Autodesk Fusion 360 part; units mm, degrees
(part 2 of 2)
equation "outer_t = skin_t + bond_t + frame_t" comment "DECIDED: PM ruling 2026-10-31: ACP 3 + bond line 3 + frame 40, walls and ceiling (was 43)"
equation "cav_gap = 4 mm" comment "DECIDED: D-16, D-42: the gap between the outer panel and the lining cassette in the wall and ceiling stack"
equation "cass_t = 34 mm" comment "SOURCE: layout study B1 final list L-CASS 34 (tray + 25 gap + felt 9)"
equation "stack_t = outer_t + cav_gap + cass_t" comment "CALCULATION: D-16, D-42 stack, walls and ceiling: outer panel + cavity gap + cassette (PM ruling 2026-10-31 on outer_t)"
equation "wall_depth = 1495 mm" comment "DECIDED: PM ruling pass C: side walls start at the decor back plate (Y -645), as v1 (1496)"
equation "lin_gap = 4 mm" comment "ASSUMPTION: PM ruling pass C: gap above the upper side linings so they stay floating (= the 4 mm stack gap)"
equation "seam_gap = 2.26 mm" comment "DECIDED: PM ruling 2026-10-31 (Mechanical Checker F-001, F-005): the Joints Engineer's 2.26 mm at all nine site seam types, set by a metal stop (1.5 stop washer + 0.76 rivnut head; joints register section 2.8)"
equation "floor_t = 0 mm" comment "DECIDED: D-132 (PM ruling 2026-11-01): no floor; people stand on the room floor (was 9)"
equation "thresh_h = 0 mm" comment "DECIDED: D-132 (PM ruling 2026-11-01): no threshold, no step at the door; the door's drop seal closes on the room floor (was 13)"
equation "thresh_d = 60 mm" comment "SOURCE: layout study B1 list B-THRESH 1176 x 60 x 20"
equation "decor_d = 205 mm" comment "SOURCE: v1 geometry per the PM ruling on D-39 (as v1; the drawings win): v1 decor-frame drawing frames 191 (left) and 197 (right) deep plus ACP and back plate = the v1 STEP shell, Y -850 to -645 = 205. D-39 and the B1 list say 230-235 (v1 BOM); see BUILD-RECORD-P02"
equation "dl_w = 278 mm" comment "SOURCE: B1 list F-DL 278 (v1 BOM DL)"
equation "dr_w = 1016 mm" comment "SOURCE: B1 list F-DR 1016 (v1 STEP solid 78)"
equation "dt_w = 1697 mm" comment "SOURCE: B1 list F-DT 1697 (v1 BOM DT)"
equation "dt_h = 280 mm" comment "SOURCE: B1 list F-DT 280"
equation "door_w = 1176 mm" comment "DECIDED: D-46"
equation "door_h = 2011 mm" comment "SOURCE: B1 list F-GLASS-DOOR 2011; v1 STEP solid 238"
equation "glass_t = 8.76 mm" comment "DECIDED: D-46 (4+4 laminate)"
equation "glass_y = 699 mm" comment "SOURCE: v1 STEP solid 238 centre Y = -699 (layout study data)"
equation "kick_d = 20 mm" comment "ASSUMPTION: kick strip envelope depth (D-40 gives the height only)"
equation "kick_gap = 7 mm" comment "SOURCE: FRONT door unit: 7 mm running gap under the kick strip for the drop seal (Mechanical Checker F-002 on P03); since D-132 the PM puts the kick strip's bottom on the band's bottom line, glide_h, so the skeleton's kick envelope no longer uses it"
equation "fr_dz = 17 mm" comment "CALCULATION: v1 front top 2417 (v2 frame) - pod_h 2400"
equation "door_xl = 289 mm" comment "SOURCE: V1-FRONT-FACETS: door left edge X -961 = -1250 + 289"
equation "door_xbr = 1464 mm" comment "SOURCE: V1-FRONT-FACETS: door bottom-right X 214"
equation "door_xtr = 1182 mm" comment "SOURCE: V1-FRONT-FACETS: door top-right X -68"
equation "door_zb = 122 mm - fr_dz" comment "SOURCE: V1-FRONT-FACETS: door bottom Z 122"
equation "door_zt = 2133 mm - fr_dz" comment "SOURCE: V1-FRONT-FACETS: door top Z 2133"
equation "fix_xbl = door_xbr + ( door_zb - fix_zb ) * ( door_xbr - door_xtr ) / ( door_zt - door_zb ) + glass_gap * sqrt(( door_xbr - door_xtr ) * ( door_xbr - door_xtr ) + ( door_zt - door_zb ) * ( door_zt - door_zb )) / ( door_zt - door_zb )" comment "CALCULATION: F-014: fixed glass bottom-left, on the line glass_gap from the door's slanted edge (was v1's 1468)"
equation "fix_xbr = 302 mm" comment "SOURCE: V1-FRONT-FACETS: fixed glass bottom-right X 948 = 1250 - 302"
equation "fix_xk = 501 mm" comment "SOURCE: V1-FRONT-FACETS: fixed glass knee X 749 = 1250 - 501"
equation "fix_zk = 1538 mm - fr_dz" comment "SOURCE: V1-FRONT-FACETS: fixed glass knee Z 1538"
equation "fix_xtr = 1480 mm" comment "SOURCE: V1-FRONT-FACETS: fixed glass top-right X 230 = -1250 + 1480"
equation "fix_xtl = door_xbr + ( door_zb - fix_zt ) * ( door_xbr - door_xtr ) / ( door_zt - door_zb ) + glass_gap * sqrt(( door_xbr - door_xtr ) * ( door_xbr - door_xtr ) + ( door_zt - door_zb ) * ( door_zt - d"
equation "fix_zb = 119 mm - fr_dz" comment "SOURCE: V1-FRONT-FACETS: fixed glass bottom Z 119"
equation "fix_zt = 2136 mm - fr_dz" comment "SOURCE: V1-FRONT-FACETS: fixed glass top Z 2136"
equation "dt_zb = 2137 mm - fr_dz" comment "SOURCE: V1-FRONT-FACETS: DT and DR edge above the glass Z 2137"
equation "ch_zlo = 2217 mm - fr_dz" comment "SOURCE: V1-FRONT-FACETS: top chamfer front edge Z 2217 at Y -848"
equation "ch_yb = 672 mm" comment "SOURCE: V1-FRONT-FACETS: top chamfer back edge Y -672"
equation "dl_x2 = 92 mm" comment "SOURCE: V1-FRONT-FACETS: DL facet knee X -1158 = -1250 + 92"
equation "dl_y2 = 752 mm" comment "SOURCE: V1-FRONT-FACETS: DL facet knee Y -752"
equation "dl_x3 = 271 mm" comment "SOURCE: V1-FRONT-FACETS: DL front corner X -979"
equation "dl_y3 = 844 mm" comment "SOURCE: V1-FRONT-FACETS: DL front corner Y -844"
equation "dl_y1 = 670 mm" comment "SOURCE: V1-FRONT-FACETS: DL outer facet start Y -670"
equation "dl_zo = 2414 mm - fr_dz" comment "SOURCE: V1-FRONT-FACETS: DL top at the outer corner Z 2414"
equation "dt_x2 = 281 mm" comment "SOURCE: V1-FRONT-FACETS: DT lower facet left X -969 = -1250 + 281"
equation "dt_y2 = 767 mm" comment "SOURCE: V1-FRONT-FACETS: DT lower facet left Y -767"
equation "dt_y3 = 753 mm" comment "SOURCE: V1-FRONT-FACETS: DT lower facet outer Y -753 at X -1154"
equation "dr_xc = 198 mm" comment "SOURCE: V1-FRONT-FACETS: DR corner facet front X 1052 = 1250 - 198"
equation "dt_xr = 1699 mm" comment "SOURCE: V1-FRONT-FACETS: DT/DR joint at the top, X 449 = -1250 + 1699 (PM ruling pass C)"
equation "dr_yc = 672 mm" comment "SOURCE: V1-FRONT-FACETS: DR corner facet back Y -672"
equation "wall_z0 = glide_h + band_h" comment "CALCULATION: base band top: glides + band"
equation "panel_z0 = wall_z0 + seam_gap" comment "CALCULATION: walls stand one seam_gap above the band top (joints register 2.8, IF-01)"
equation "wall_h = pod_h - wall_z0" comment "CALCULATION: 2290 = layout study v2_model wall_h"
equation "side_h = ( wall_h - 2 * seam_gap ) / 2" comment "CALCULATION: D-23: 2 sheets per side wall; the gap on the band and the horizontal seam (joints register 2.8)"
equation "side_l = wall_depth - seam_gap" comment "CALCULATION: side panel length along Y: the seam_gap at the decor's back plate (joints register 2.8, IF-07)"
equation "back_oh = pod_h - outer_t - seam_gap - panel_z0" comment "CALCULATION: PM ruling 2026-10-31 (pass D, F-004): the back outer frames run up to the ceiling frame (pod_h - outer_t), less the seam_gap under it, closing the slot at the back top edge"
equation "back_ph = ( back_oh - seam_gap ) / 2" comment "CALCULATION: D-23: 4 sheets on the back, two equal rows with one seam_gap between them (joints register 2.8); the lower back linings match the lower row, as on the side walls"
equation "half_pw = ( pod_w - 2 * outer_t - 3 * seam_gap ) / 2" comment "CALCULATION: SKIN width of each back and ceiling panel: two skins and three seam_gap seams between the side frames (F-001, joints register 2.8)"
equation "inner_w = pod_w - 2 * stack_t" comment "CALCULATION: inside width between the side linings"
equation "d66 = panel_z0"
equation "d68 = ( -pod_w / 2 + outer_t ) - ( -pod_w / 2 )"
equation "d69 = ( pod_d / 2 ) - ( pod_d / 2 - wall_depth + seam_gap )"
equation "d70 = abs(-pod_w / 2)"
equation "d71 = abs(pod_d / 2 - wall_depth + seam_gap)"
equation "d72 = ( panel_z0 + side_h ) - ( panel_z0 )"
equation "d74 = panel_z0"
equation "d76 = ( -pod_w / 2 + stack_t ) - ( -pod_w / 2 + stack_t - cass_t )"
equation "d77 = ( pod_d / 2 - stack_t + cass_t ) - ( pod_d / 2 - wall_depth )"
equation "d78 = abs(-pod_w / 2 + stack_t - cass_t)"
equation "d79 = abs(pod_d / 2 - wall_depth)"
equation "d80 = ( panel_z0 + side_h ) - ( panel_z0 )"
equation "d82 = panel_z0 + side_h + seam_gap"
equation "d84 = ( -pod_w / 2 + outer_t ) - ( -pod_w / 2 )"
equation "d85 = ( pod_d / 2 ) - ( pod_d / 2 - wall_depth + seam_gap )"
equation "d86 = abs(-pod_w / 2)"
equation "d87 = abs(pod_d / 2 - wall_depth + seam_gap)"
equation "d88 = ( pod_h ) - ( panel_z0 + side_h + seam_gap )"
equation "d90 = panel_z0 + side_h + seam_gap"
equation "d92 = ( -pod_w / 2 + stack_t ) - ( -pod_w / 2 + stack_t - cass_t )"
equation "d93 = ( pod_d / 2 - stack_t + cass_t ) - ( pod_d / 2 - wall_depth )"
equation "d94 = abs(-pod_w / 2 + stack_t - cass_t)"
equation "d95 = abs(pod_d / 2 - wall_depth)"
equation "d96 = ( pod_h - outer_t - lin_gap ) - ( panel_z0 + side_h + seam_gap )"
equation "d98 = panel_z0"
equation "d100 = ( pod_w / 2 ) - ( pod_w / 2 - outer_t )"
equation "d101 = ( pod_d / 2 ) - ( pod_d / 2 - wall_depth + seam_gap )"
equation "d102 = abs(pod_w / 2 - outer_t)"
equation "d103 = abs(pod_d / 2 - wall_depth + seam_gap)"
equation "d104 = ( panel_z0 + side_h ) - ( panel_z0 )"
equation "d106 = panel_z0"
equation "d108 = ( pod_w / 2 - stack_t + cass_t ) - ( pod_w / 2 - stack_t )"
equation "d109 = ( pod_d / 2 - stack_t + cass_t ) - ( pod_d / 2 - wall_depth )"
equation "d110 = abs(pod_w / 2 - stack_t)"
equation "d111 = abs(pod_d / 2 - wall_depth)"
equation "d112 = ( panel_z0 + side_h ) - ( panel_z0 )"
equation "d114 = panel_z0 + side_h + seam_gap"
equation "d116 = ( pod_w / 2 ) - ( pod_w / 2 - outer_t )"
equation "d117 = ( pod_d / 2 ) - ( pod_d / 2 - wall_depth + seam_gap )"
equation "d118 = abs(pod_w / 2 - outer_t)"
equation "d119 = abs(pod_d / 2 - wall_depth + seam_gap)"
equation "d120 = ( pod_h ) - ( panel_z0 + side_h + seam_gap )"
equation "d122 = panel_z0 + side_h + seam_gap"
equation "d124 = ( pod_w / 2 - stack_t + cass_t ) - ( pod_w / 2 - stack_t )"
equation "d125 = ( pod_d / 2 - stack_t + cass_t ) - ( pod_d / 2 - wall_depth )"
equation "d126 = abs(pod_w / 2 - stack_t)"
equation "d127 = abs(pod_d / 2 - wall_depth)"
equation "d128 = ( pod_h - outer_t - lin_gap ) - ( panel_z0 + side_h + seam_gap )"
equation "d130 = panel_z0"
equation "d132 = ( -pod_w / 2 + outer_t + seam_gap + half_pw ) - ( -pod_w / 2 + outer_t + seam_gap )"
equation "d133 = ( pod_d / 2 ) - ( pod_d / 2 - outer_t )"
equation "d134 = abs(-pod_w / 2 + outer_t + seam_gap)"
equation "d135 = abs(pod_d / 2 - outer_t)"
equation "d136 = ( panel_z0 + back_ph ) - ( panel_z0 )"
equation "d138 = panel_z0"
equation "d140 = ( 0 mm ) - ( -pod_w / 2 + stack_t )"
equation "d141 = ( pod_d / 2 - stack_t + cass_t ) - ( pod_d / 2 - stack_t )"
equation "d142 = abs(-pod_w / 2 + stack_t)"
equation "d143 = abs(pod_d / 2 - stack_t)"
equation "d144 = ( panel_z0 + back_ph ) - ( panel_z0 )"
equation "d146 = panel_z0"
equation "d148 = ( pod_w / 2 - outer_t - seam_gap ) - ( pod_w / 2 - outer_t - seam_gap - half_pw )"
equation "d149 = ( pod_d / 2 ) - ( pod_d / 2 - outer_t )"
equation "d150 = abs(pod_w / 2 - outer_t - seam_gap - half_pw)"
equation "d151 = abs(pod_d / 2 - outer_t)"
equation "d152 = ( panel_z0 + back_ph ) - ( panel_z0 )"
equation "d154 = panel_z0"
equation "d156 = ( pod_w / 2 - stack_t ) - ( 0 mm )"
equation "d157 = ( pod_d / 2 - stack_t + cass_t ) - ( pod_d / 2 - stack_t )"
equation "d158 = abs(pod_d / 2 - stack_t)"
equation "d159 = ( panel_z0 + back_ph ) - ( panel_z0 )"
equation "d161 = panel_z0 + back_ph + seam_gap"
equation "d163 = ( -pod_w / 2 + outer_t + seam_gap + half_pw ) - ( -pod_w / 2 + outer_t + seam_gap )"
equation "d164 = ( pod_d / 2 ) - ( pod_d / 2 - outer_t )"
equation "d165 = abs(-pod_w / 2 + outer_t + seam_gap)"
equation "d166 = abs(pod_d / 2 - outer_t)"
equation "d167 = ( panel_z0 + back_oh ) - ( panel_z0 + back_ph + seam_gap )"
equation "d169 = panel_z0 + back_ph + seam_gap"
equation "d171 = ( 0 mm ) - ( -pod_w / 2 + stack_t )"
equation "d172 = ( pod_d / 2 - stack_t + cass_t ) - ( pod_d / 2 - stack_t )"
equation "d173 = abs(-pod_w / 2 + stack_t)"
equation "d174 = abs(pod_d / 2 - stack_t)"
equation "d175 = ( pod_h - outer_t - lin_gap ) - ( panel_z0 + back_ph + seam_gap )"
equation "d177 = panel_z0 + back_ph + seam_gap"
equation "d179 = ( pod_w / 2 - outer_t - seam_gap ) - ( pod_w / 2 - outer_t - seam_gap - half_pw )"
equation "d180 = ( pod_d / 2 ) - ( pod_d / 2 - outer_t )"
equation "d181 = abs(pod_w / 2 - outer_t - seam_gap - half_pw)"
equation "d182 = abs(pod_d / 2 - outer_t)"
equation "d183 = ( panel_z0 + back_oh ) - ( panel_z0 + back_ph + seam_gap )"
equation "d185 = panel_z0 + back_ph + seam_gap"
equation "d187 = ( pod_w / 2 - stack_t ) - ( 0 mm )"
equation "d188 = ( pod_d / 2 - stack_t + cass_t ) - ( pod_d / 2 - stack_t )"
equation "d189 = abs(pod_d / 2 - stack_t)"
equation "d190 = ( pod_h - outer_t - lin_gap ) - ( panel_z0 + back_ph + seam_gap )"
equation "d192 = pod_h - outer_t"
equation "d194 = ( -pod_w / 2 + outer_t + seam_gap + half_pw ) - ( -pod_w / 2 + outer_t + seam_gap )"
equation "d195 = ( pod_d / 2 ) - ( pod_d / 2 - wall_depth )"
equation "d196 = abs(-pod_w / 2 + outer_t + seam_gap)"
equation "d197 = abs(pod_d / 2 - wall_depth)"
equation "d198 = ( pod_h ) - ( pod_h - outer_t )"
equation "d200 = pod_h - stack_t"
equation "d202 = ( 0 mm ) - ( -pod_w / 2 + stack_t )"
equation "d203 = ( pod_d / 2 - stack_t ) - ( pod_d / 2 - wall_depth )"
equation "d204 = abs(-pod_w / 2 + stack_t)"
equation "d205 = abs(pod_d / 2 - wall_depth)"
equation "d206 = ( pod_h - stack_t + cass_t ) - ( pod_h - stack_t )"
equation "d214 = pod_h - outer_t"
equation "d216 = ( pod_w / 2 - outer_t - seam_gap ) - ( pod_w / 2 - outer_t - seam_gap - half_pw )"
equation "d217 = ( pod_d / 2 ) - ( pod_d / 2 - wall_depth )"
equation "d218 = abs(pod_w / 2 - outer_t - seam_gap - half_pw)"
equation "d219 = abs(pod_d / 2 - wall_depth)"
equation "d220 = ( pod_h ) - ( pod_h - outer_t )"
equation "d222 = pod_h - stack_t"
equation "d224 = ( pod_w / 2 - stack_t ) - ( 0 mm )"
equation "d225 = ( pod_d / 2 - stack_t ) - ( pod_d / 2 - wall_depth )"
equation "d226 = abs(pod_d / 2 - wall_depth)"
equation "d227 = ( pod_h - stack_t + cass_t ) - ( pod_h - stack_t )"
equation "d234 = glide_h"
equation "d236 = ( pod_w / 2 - band_t ) - ( -pod_w / 2 + band_t )"
equation "d237 = ( pod_d / 2 ) - ( pod_d / 2 - band_t )"
equation "d238 = abs(-pod_w / 2 + band_t)"
equation "d239 = abs(pod_d / 2 - band_t)"
equation "d240 = ( wall_z0 ) - ( glide_h )"
equation "d248 = glide_h"
equation "d250 = ( -pod_w / 2 + door_xbr ) - ( -pod_w / 2 + door_xl )"
equation "d251 = ( -glass_y + kick_d / 2 ) - ( -glass_y - kick_d / 2 )"
equation "d252 = abs(-pod_w / 2 + door_xl)"
equation "d253 = abs(-glass_y - kick_d / 2)"
equation "d254 = ( door_zb ) - ( glide_h )"
equation "d256 = abs(-pod_w / 2)"
equation "d257 = abs(-pod_w / 2 + dl_x2)"
equation "d258 = abs(-pod_w / 2 + dl_x3)"
equation "d259 = abs(-pod_w / 2 + dl_w)"
equation "d260 = abs(-dl_y1)"
equation "d261 = abs(-dl_y2)"
equation "d262 = abs(-dl_y3)"
equation "d263 = abs(-pod_d / 2 + decor_d)"
equation "d264 = ( wall_z0 ) * ( 1 )"
equation "d265 = ( pod_h ) - ( wall_z0 )"
equation "d267 = abs(-pod_w / 2 + dl_w)"
equation "d268 = abs(-pod_w / 2)"
equation "d269 = abs(dl_zo)"
equation "d270 = abs(dt_zb)"
equation "d271 = abs(pod_h)"
equation "d272 = ( -pod_d / 2 ) * ( 1 )"
equation "d273 = ( -pod_d / 2 + decor_d ) - ( -pod_d / 2 )"
equation "d275 = abs(-pod_w / 2)"
equation "d276 = abs(-pod_w / 2 + dl_x2 + 4 mm)"
equation "d277 = abs(-pod_w / 2 + dt_x2)"
equation "d278 = abs(-pod_w / 2 + fix_xtr)"
equation "d279 = abs(-pod_w / 2 + dt_xr)"
equation "d280 = abs(-dl_y1)"
equation "d281 = abs(-dt_y3)"
equation "d282 = abs(-dt_y2)"
equation "d283 = abs(-pod_d / 2)"
equation "d284 = abs(-ch_yb)"
equation "d285 = abs(-pod_d / 2 + decor_d)"
equation "d286 = ( dt_zb ) * ( 1 )"
equation "d287 = ( pod_h ) - ( dt_zb )"
equation "d289 = abs(-pod_w / 2 + dl_w)"
equation "d290 = abs(-pod_w / 2)"
equation "d291 = abs(dt_zb)"
equation "d292 = abs(dl_zo)"
equation "d293 = ( -pod_d / 2 ) * ( 1 )"
equation "d294 = ( -pod_d / 2 + decor_d ) - ( -pod_d / 2 )"
equation "d296 = abs(ch_zlo)"
equation "d297 = abs(pod_h)"
equation "d298 = abs(-ch_yb)"
equation "d299 = abs(-pod_d / 2)"
equation "d300 = ( -pod_w / 2 ) * ( 1 )"
equation "d301 = ( pod_w / 2 ) - ( -pod_w / 2 )"
equation "d303 = abs(pod_w / 2 - fix_xbr)"
equation "d304 = abs(pod_w / 2)"
equation "d305 = abs(-pod_w / 2 + fix_xtr)"
equation "d306 = abs(pod_w / 2 - fix_xk)"
equation "d307 = abs(fix_zb)"
equation "d308 = abs(pod_h)"
equation "d309 = abs(dt_zb)"
equation "d310 = abs(fix_zk)"
equation "d311 = ( -pod_d / 2 ) * ( 1 )"
equation "d312 = ( -pod_d / 2 + decor_d ) - ( -pod_d / 2 )"
equation "d314 = abs(pod_w / 2 - dr_xc)"
equation "d315 = abs(pod_w / 2)"
equation "d316 = abs(-dr_yc)"
equation "d317 = abs(-pod_d / 2)"
equation "d318 = ( 0 mm ) * ( 1 )"
equation "d319 = ( pod_h ) - ( 0 mm )"
equation "d321 = abs(-pod_w / 2 + dt_xr)"
equation "d322 = abs(-pod_w / 2 + fix_xtr)"
equation "d323 = abs(-pod_d / 2)"
equation "d324 = abs(-ch_yb)"
equation "d325 = abs(-pod_d / 2 + decor_d)"
equation "d326 = ( dt_zb ) * ( 1 )"
equation "d327 = ( pod_h ) - ( dt_zb )"
equation "d329 = abs(ch_zlo)"
equation "d330 = abs(pod_h)"
equation "d331 = abs(-ch_yb)"
equation "d332 = abs(-pod_d / 2)"
equation "d333 = ( -pod_w / 2 ) * ( 1 )"
equation "d334 = ( pod_w / 2 ) - ( -pod_w / 2 )"
equation "d336 = abs(pod_w / 2)"
equation "d337 = abs(-pod_w / 2 + fix_xtr)"
equation "d338 = abs(-pod_d / 2)"
equation "d339 = abs(-pod_d / 2 + decor_d)"
equation "d340 = ( 0 mm ) * ( 1 )"
equation "d341 = ( wall_z0 ) - ( 0 mm )"
equation "d343 = abs(-pod_w / 2 + door_xbr)"
equation "d344 = abs(-pod_w / 2 + door_xtr)"
equation "d345 = abs(-pod_w / 2 + door_xl)"
equation "d346 = abs(door_zb)"
equation "d347 = abs(door_zt)"
equation "d348 = ( -glass_y - glass_t / 2 ) * ( 1 )"
equation "d349 = ( -glass_y + glass_t / 2 ) - ( -glass_y - glass_t / 2 )"
equation "d351 = abs(-pod_w / 2 + fix_xbl)"
equation "d352 = abs(pod_w / 2 - fix_xbr)"
equation "d353 = abs(pod_w / 2 - fix_xk)"
equation "d354 = abs(-pod_w / 2 + fix_xtr)"
equation "d355 = abs(-pod_w / 2 + fix_xtl)"
equation "d356 = abs(fix_zb)"
equation "d357 = abs(fix_zk)"
equation "d358 = abs(fix_zt)"
equation "d359 = ( -glass_y - glass_t / 2 ) * ( 1 )"
equation "d360 = ( -glass_y + glass_t / 2 ) - ( -glass_y - glass_t / 2 )"
equation "d362 = abs(-pod_w / 2)"
equation "d363 = abs(-pod_w / 2 + band_t)"
equation "d364 = abs(-dl_y1)"
equation "d365 = abs(pod_d / 2)"
equation "d366 = abs(-dl_y1 + band_t * ( sqrt(( dl_x2 ) * ( dl_x2 ) + ( ( dl_y2 - dl_y1 ) ) * ( ( dl_y2 - dl_y1 ) )) - ( dl_y2 - dl_y1 ) ) / dl_x2)"
equation "d367 = ( glide_h ) * ( 1 )"
equation "d368 = ( wall_z0 ) - ( glide_h )"
equation "d370 = abs(-pod_w / 2)"
equation "d371 = abs(-pod_w / 2 + dl_x2)"
equation "d372 = abs(-pod_w / 2 + dl_x3)"
equation "d373 = abs(-pod_w / 2 + dl_w)"
equation "d374 = abs(-pod_w / 2 + dl_x2 + band_t * ( ( dl_y2 - dl_y1 ) / sqrt(( dl_x2 ) * ( dl_x2 ) + ( ( dl_y2 - dl_y1 ) ) * ( ( dl_y2 - dl_y1 ) )) + ( dl_y3 - dl_y2 ) / sqrt(( ( dl_x3 - dl_x2 ) ) * ( ( dl_x3 - dl_x2 ) ) + ( ( dl_y3 - dl_y2 ) ) * ( ( dl_y3 - dl_y2 ) )) ) / ( 1 + ( ( ( dl_y2 - dl_y1 ) ) * ( ( dl_y3 - dl_y2 ) ) + ( dl_x2 ) * ( ( dl_x3 - dl_x2 ) ) ) / ( ( sqrt(( dl_x2 ) * ( dl_x2 ) + ( ( dl_y2 - dl_y1 ) ) * ( ( dl_y2 - dl_y1 ) )) ) * ( sqrt(( ( dl_x3 - dl_x2 ) ) * ( ( dl_x3 - dl_x2 ) ) + ( ( dl_y3 - dl_y2 ) ) * ( ( dl_y3 - dl_y2 ) )) ) ) ))"
equation "d375 = abs(-pod_w / 2 + band_t)"
equation "d376 = abs(-dl_y1)"
equation "d377 = abs(-dl_y2)"
equation "d378 = abs(-dl_y3)"
equation "d379 = abs(-dl_y2 + ( band_t * sqrt(( ( dl_x3 - dl_x2 ) ) * ( ( dl_x3 - dl_x2 ) ) + ( ( dl_y3 - dl_y2 ) ) * ( ( dl_y3 - dl_y2 ) )) - ( dl_y3 - dl_y2 ) * ( dl_w - dl_x2 ) ) / ( dl_x3 - dl_x2 ))"
equation "d380 = abs(-dl_y2 + band_t * ( dl_x2 / sqrt(( dl_x2 ) * ( dl_x2 ) + ( ( dl_y2 - dl_y1 ) ) * ( ( dl_y2 - dl_y1 ) )) + ( dl_x3 - dl_x2 ) / sqrt(( ( dl_x3 - dl_x2 ) ) * ( ( dl_x3 - dl_x2 ) ) + ( ( dl_y3 - dl_y2 ) ) * ( ( dl_y3 - dl_y2 ) )) ) / ( 1 + ( ( ( dl_y2 - dl_y1 ) ) * ( ( dl_y3 - dl_y2 ) ) + ( dl_x2 ) * ( ( dl_x3 - dl_x2 ) ) ) / ( ( sqrt(( dl_x2 ) * ( dl_x2 ) + ( ( dl_y2 - dl_y1 ) ) * ( ( dl_y2 - dl_y1 ) )) ) * ( sqrt(( ( dl_x3 - dl_x2 ) ) * ( ( dl_x3 - dl_x2 ) ) + ( ( dl_y3 - dl_y2 ) ) * ( ( dl_y3 - dl_y2 ) )) ) ) ))"
equation "d381 = abs(-dl_y1 + band_t * ( sqrt(( dl_x2 ) * ( dl_x2 ) + ( ( dl_y2 - dl_y1 ) ) * ( ( dl_y2 - dl_y1 ) )) - ( dl_y2 - dl_y1 ) ) / dl_x2)"
equation "d382 = ( glide_h ) * ( 1 )"
equation "d383 = ( wall_z0 ) - ( glide_h )"
equation "d385 = abs(pod_w / 2 - dr_xc)"
equation "d386 = abs(pod_w / 2)"
equation "d387 = abs(pod_w / 2 - band_t)"
equation "d388 = abs(pod_w / 2 - dr_xc - band_t * ( pod_d / 2 - dr_yc ) / ( sqrt(( dr_xc ) * ( dr_xc ) + ( ( pod_d / 2 - dr_yc ) ) * ( ( pod_d / 2 - dr_yc ) )) + dr_xc ))"
equation "d389 = abs(-pod_w / 2 + fix_xbl)"
equation "d390 = abs(-pod_d / 2)"
equation "d391 = abs(-dr_yc)"
equation "d392 = abs(-dr_yc + band_t * ( sqrt(( dr_xc ) * ( dr_xc ) + ( ( pod_d / 2 - dr_yc ) ) * ( ( pod_d / 2 - dr_yc ) )) - ( pod_d / 2 - dr_yc ) ) / dr_xc)"
equation "d393 = abs(-pod_d / 2 + band_t)"
equation "d394 = ( glide_h ) * ( 1 )"
equation "d395 = ( wall_z0 ) - ( glide_h )"
equation "d397 = abs(pod_w / 2)"
equation "d398 = abs(pod_w / 2 - band_t)"
equation "d399 = abs(-dr_yc)"
equation "d400 = abs(pod_d / 2)"
equation "d401 = abs(-dr_yc + band_t * ( sqrt(( dr_xc ) * ( dr_xc ) + ( ( pod_d / 2 - dr_yc ) ) * ( ( pod_d / 2 - dr_yc ) )) - ( pod_d / 2 - dr_yc ) ) / dr_xc)"
equation "d402 = ( glide_h ) * ( 1 )"
equation "d403 = ( wall_z0 ) - ( glide_h )"
equation "glass_gap = 4 mm" comment "DECIDED: PM ruling 2026-10-31 on Mechanical Checker F-014: the fixed glass's free edge runs parallel to the door's slanted edge, 4.0 mm away (FRONT's glass in PR #28 is the reference)"
equation "base_bolt_edge = bolt_edge_inset" comment "DECIDED: J-BASE-01 wall to band: the edge rule (kept by this name for parts already linked)"
equation "n_base_bolt = 4" comment "DECIDED: PM ruling 2026-10-31, J-BASE-01: bolts per panel along the band, evenly spaced"
equation "base_spigot_inset = spigot_inset" comment "DECIDED: J-BASE-01: the spigot rule (kept by this name for parts already linked)"
equation "side_base_pitch = ( side_l - 2 * base_bolt_edge ) / ( n_base_bolt - 1 )" comment "CALCULATION: J-BASE-01 bolt pitch along a side panel"
equation "back_base_pitch = ( half_fw - 2 * base_bolt_edge ) / ( n_base_bolt - 1 )" comment "DECIDED: PM ruling 2026-10-31 (Reviewer 5 P2 on #58): J-BASE-01 pitch along a back panel, measured on the FRAME (half_fw), where the bolts go; 'panel end' means the frame end"
equation "skin_t = 3 mm" comment "DECIDED: ACP skin, walls and ceiling (D-16; PM ruling 2026-10-31 on outer_t)"
equation "bond_t = 3 mm" comment "DECIDED: bond line between the ACP and the frame (PM ruling 2026-10-31 on outer_t)"
equation "frame_t = 40 mm" comment "DECIDED: aluminium frame tube depth, walls and ceiling (PM ruling 2026-10-31 on outer_t)"
equation "close_gap = 5.5 mm" comment "DECIDED: PM ruling 2026-10-31 (joints register, F-011/F-012): frame gap at the closing seams B1-B2, B3-B4 and C1-C2, which have no hard stop (slotted holes, thicker gasket)"
equation "half_fw = ( pod_w - 2 * outer_t - 2 * seam_gap - close_gap ) / 2" comment "CALCULATION: FRAME width of each back and ceiling panel: the skins overhang their frames by half_pw - half_fw at the closing seam (PM ruling 2026-10-31)"
equation "bolt_edge_inset = 220 mm" comment "DECIDED: PM ruling 2026-10-31: on every bolted edge the end bolts sit this far in from each panel end (the FRAME end, where the bolts go), the rest evenly spaced"
equation "spigot_inset = 100 mm" comment "DECIDED: PM ruling 2026-10-31: locating spigots this far in from each panel end (round hole at one end, slot at the other)"
equation "ceil_bolt_z = pod_h - outer_t + frame_t / 2" comment "DECIDED: PM ruling 2026-10-31, J-CEIL-01 wall to ceiling: the bolt line on the ceiling frame's centre (Z 2374)"
equation "n_ceil_side_bolt = 4" comment "DECIDED: PM ruling 2026-10-31, J-CEIL-01: bolts along each side wall top"
equation "n_ceil_back_bolt = 4" comment "DECIDED: PM ruling 2026-10-31, J-CEIL-01: bolts along each back panel top, like the base (pitch about 253, every edge 350 or less; joints register: 82 bolts in all)"
equation "ceil_side_pitch = ( wall_depth - 2 * bolt_edge_inset ) / ( n_ceil_side_bolt - 1 )" comment "DECIDED: PM ruling 2026-10-31 (joints register): J-CEIL-01 pitch along a side wall top, over the ceiling's length (was over the side panel's)"
equation "ceil_back_pitch = ( half_fw - 2 * bolt_edge_inset ) / ( n_ceil_back_bolt - 1 )" comment "DECIDED: PM ruling 2026-10-31 (joints register): J-CEIL-01 pitch along a back panel top, on the frame (half_fw)"
equation "mat_t = 0 mm" comment "DECIDED: D-132 (PM ruling 2026-11-01): no floor, so no floor mat (was 3, D-72)"
equation "floor_top = mat_t + floor_t" comment "CALCULATION: the floor top: Z 0, the room floor itself (D-132: no floor; was Z 12)"
equation "base_side_y0 = pod_d / 2 - wall_depth + seam_gap" comment "CALCULATION: J-BASE-01: side bolt lines start at the side panel's front end (first bolt base_bolt_edge further on)"
equation "base_back_x0 = pod_w / 2 - outer_t - seam_gap" comment "CALCULATION: J-BASE-01: back bolt lines start at each back FRAME's outer end, X -/+ this (first bolt base_bolt_edge further in)"
equation "ceil_side_y0 = pod_d / 2 - wall_depth" comment "DECIDED: PM ruling 2026-10-31 (joints register): J-CEIL-01 side bolt lines start at Y -645, measured along the ceiling (first bolt bolt_edge_inset further on)"
equation "ceil_back_x0 = pod_w / 2 - outer_t - seam_gap" comment "DECIDED: PM ruling 2026-10-31 (joints register): J-CEIL-01 back bolt lines start at each back frame's outer end, X -/+ this"
equation "d429 = mat_t"
equation "d430 = ( 0 mm ) - ( -pod_w / 2 + band_t )"
equation "d431 = ( pod_d / 2 - band_t ) - ( pod_d / 2 - wall_depth )"
equation "d432 = abs(-pod_w / 2 + band_t)"
equation "d433 = abs(pod_d / 2 - wall_depth)"
equation "d434 = ( mat_t ) - ( 0 mm )"
equation "d436 = mat_t"
equation "d437 = ( pod_w / 2 - band_t ) - ( 0 mm )"
equation "d438 = ( pod_d / 2 - band_t ) - ( pod_d / 2 - wall_depth )"
equation "d439 = abs(pod_d / 2 - wall_depth)"
equation "d440 = ( mat_t ) - ( 0 mm )"
named bodies: "L1 ENVELOPE", "L1-CASS ENVELOPE", "L2 ENVELOPE", "L2-CASS ENVELOPE", "R1 ENVELOPE", "R1-CASS ENVELOPE", "R2 ENVELOPE", "R2-CASS ENVELOPE", "B1 ENVELOPE", "B1-CASS ENVELOPE", "B2 ENVELOPE", "B2-CASS ENVELOPE", "B3 ENVELOPE", "B3-CASS ENVELOPE", "B4 ENVELOPE", "B4-CASS ENVELOPE", "C1 ENVELOPE", "C1-CASS ENVELOPE", "C2 ENVELOPE", "C2-CASS ENVELOPE", "BAND-BACK ENVELOPE", "KICK ENVELOPE", "DL FACETED", "DT FACETED", "DR FACETED", "DOOR GLASS", "FIXED GLASS", "BAND-L ENVELOPE", "BAND-FL ENVELOPE", "BAND-FR ENVELOPE", "BAND-R ENVELOPE"
